case (Autodesk Fusion 360 design; units mm, degrees)
Autodesk Fusion 360 part; units mm, degrees
sketch "Sketch1" plane through (0, 0, 0) normal (0, 1, 0) x (1, 0, 0)
  line L0 (-83.15, 7.15) -> (83.15, 7.15)
  line L1 (83.15, 7.15) -> (83.15, -7.15)
  line L2 (83.15, -7.15) -> (-83.15, -7.15)
  line L3 (-83.15, -7.15) -> (-83.15, 7.15)
  line L4 (-83.15, 7.15) -> (83.15, -7.15) construction
  line L5 (83.15, 7.15) -> (-83.15, -7.15) construction
  dimension "d1" = 166.3
  dimension "d2" = 14.3
  constraint perpendicular L0 L1
  constraint parallel L0 L2
  constraint parallel L1 L3
  constraint horizontal L0
  constraint coincident L4 origin
  constraint coincident L5 origin
  measures "d1" distance of L1.end L2.end
  measures "d2" distance of L0.end L1.end
sketch "Sketch2" plane through (0, 0, 0) normal (1, 0, 0) x (0, 0, -1)
  circle A0 centre (0, 0) radius 7.15
  line L0 (7.15, 0) -> (10.65, 0)
  line L1 (-7.15, 0) -> (-10.65, 0)
  circle A1 centre (0, 0) radius 10.65
  point P0 (7.15, 0)
  point P1 (-7.15, 0)
  dimension "d4" = 3.5
  dimension "d34" = 21.3
  constraint coincident A0.centre A1.centre
  constraint coincident A0 P0
  constraint coincident P0 L0.start
  constraint coincident P1 L1.start
  constraint coincident L0.end A1
  measures "d4" distance of P1 L1.end
  measures "d34" diameter of A1
extrude "Extrude1" add sketch "Sketch2" along normal blind 140 contours A0 L0 L1 A1 | A0 L0 L1 A1
sketch "Sketch3" plane through (140, 0, 0) normal (1, 0, 0) x (0, 0, -1)
  circle A0 centre (0, 0) radius 7.15
  circle A1 centre (0, 0) radius 10.65
  line L0 (0, 0) -> (0, -10.65)
  line L1 (0, -7.15) -> (-3, -7.15)
  line L2 (0, -7.15) -> (3, -7.15)
  line L3 (-3, -7.15) -> (-3, -8.75)
  line L4 (3, -7.15) -> (3, -8.75)
  line L5 (-3, -8.75) -> (3, -8.75)
  line L6 (-3, -7.15) -> (-3, -6)
  line L7 (3, -7.15) -> (3, -5.7361)
  dimension "d7" = 3
  dimension "d8" = 3
  dimension "d9" = 1.6
  dimension "d10" = 1.6
  constraint coincident A0.centre A1.centre
  constraint coincident A1 L0.end
  constraint vertical L0
  constraint coincident L0 L1.start
  constraint coincident A0 L1.start
  constraint perpendicular L4 L5
  constraint perpendicular L5 L6
  constraint perpendicular L2 L7
  measures "d7" distance of L1.start L1.end
  measures "d8" distance of L1.start L2.end
  measures "d9" distance of L1.end L3.end
  measures "d10" distance of L2.end L4.end
extrude "Extrude2" cut sketch "Sketch3" against normal blind 42 contours A0 L1 L6 | A0 L2 L7 | L0 L2 L4 L5 | L0 L1 L3 L5
fillet "Fillet1" radius 4 2 edges at (119, -6.4902, 3) (119, -6.4902, -3)
fillet "Fillet2" radius 2 1 edges at (98, -7.15, 0)
sketch "Sketch4" plane through (0, 0, 0) normal (-1, 0, 0) x (0, 0, 1)
  circle A0 centre (0, 0) radius 7.15
  circle A1 centre (0, 0) radius 10.65
extrude "Extrude3" add sketch "Sketch4" along normal blind 2.5 contours A0 | A1
sketch "Sketch5" plane through (140, 0, 0) normal (1, 0, 0) x (0, 0, -1)
  arc A0 (4.4888, -5.5654) -> (3, -8.6789) centre (7, -8.6789) ccw
  line L0 (3, -8.6789) -> (3, -8.75)
  line L1 (3, -8.75) -> (-3, -8.75)
  line L2 (-3, -8.75) -> (-3, -8.6789)
  arc A1 (-3, -8.6789) -> (-4.4888, -5.5654) centre (-7, -8.6789) ccw
  arc A2 (4.4888, -5.5654) -> (-4.4888, -5.5654) centre (0, 0) ccw
  circle A3 centre (0, 0) radius 10.65
  line L3 (0, 0) -> (-0.0172, 16)
  line L4 (-10.65, 0) -> (-10.65, 13.2572)
  line L5 (10.65, 0) -> (10.65, 13.2572)
  line L6 (0, 13.2572) -> (-5.0089, 13.2518)
  line L7 (0, 13.2572) -> (4.9811, 13.2626)
  line L8 (0, 9.65) -> (-6, 9.6435)
  line L9 (0, 9.65) -> (8, 9.6586)
  line L10 (-5.0089, 13.2518) -> (-5.0024, 7.1882)
  line L11 (4.9811, 13.2626) -> (4.9874, 7.3746)
  line L12 (-5.0047, 9.4008) -> (-4.9656, 11.9005)
  line L13 (4.9852, 9.4112) -> (4.9825, 11.9112)
  line L14 (-4.9656, 11.9005) -> (4.9825, 11.9112)
  line L15 (-4.9656, 11.9005) -> (-2.4667, 11.8256)
  line L16 (4.9825, 11.9112) -> (2.4836, 11.8367)
  line L17 (-2.4667, 11.8256) -> (-2.4638, 9.0524)
  line L18 (2.4836, 11.8367) -> (2.4869, 8.7914)
  line L19 (-2.4644, 9.6473) -> (-5.2621, 9.6443)
  line L20 (-5.0009, 9.6446) -> (-5.0063, 14.6446)
  line L21 (2.486, 9.6526) -> (5.4045, 9.6558)
  line L22 (4.9849, 9.6553) -> (4.9796, 14.6553)
  line L23 (-5.0063, 14.6446) -> (4.9796, 14.6553)
  line L24 (-2.4667, 11.8256) -> (-2.4706, 15.4609)
  line L25 (2.4836, 11.8367) -> (2.4796, 15.6307)
  point P0 (-10.65, 0)
  point P1 (10.65, 0)
  dimension "d17" = 2.5
  dimension "d18" = 2.5
  dimension "d19" = 2.5
  dimension "d20" = 2.5
  dimension "d21" = 5
  dimension "d22" = 5
  constraint coincident A2.centre A3.centre
  constraint coincident P0 L4.start
  constraint tangent A3 L4
  constraint vertical L4
  constraint coincident P1 L5.start
  constraint tangent A3 L5
  constraint vertical L5
  constraint perpendicular L3 L9
  constraint perpendicular L3 L8
  constraint perpendicular L3 L6
  constraint perpendicular L3 L7
  constraint perpendicular L8 L10
  constraint perpendicular L9 L11
  constraint coincident A3 L12.start
  constraint coincident L10 L12.start
  constraint coincident L11 L13.start
  constraint coincident A3 L13.start
  constraint perpendicular L13 L14
  constraint perpendicular L8 L17
  constraint perpendicular L9 L18
  constraint coincident L17 L19.start
  constraint coincident L8 L19.start
  constraint coincident L8 L19.end
  constraint coincident L19 L20.start
  constraint coincident L12 L20.start
  constraint coincident L18 L21.start
  constraint coincident L9 L21.start
  constraint coincident L9 L21.end
  constraint perpendicular L13 L21
  constraint coincident L9 L22.start
  constraint coincident L11 L22.start
  constraint perpendicular L22 L23
  constraint perpendicular L23 L24
  constraint parallel L17 L24
  constraint perpendicular L23 L25
  measures "d17" distance of L12.start L12.end
  measures "d18" distance of L13.start L13.end
  measures "d19" distance of L12.end L15.end
  measures "d20" distance of L13.end L16.end
  measures "d21" distance of L20.start L20.end
  measures "d22" distance of L22.start L22.end
extrude "Extrude4" add sketch "Sketch5" against normal blind 5 contours A3 L9 L11 L13 L21 | A3 L9 L11 L13 L16 L18 L21 L22 | A3 L8 L12 L19 | L7 L11 L14 L22 L25 | L14 L16 L25 | A3 L8 L12 L15 L17 L19 | A3 L8 L17 L19 | L6 L12 L14 L20 L24 | L7 L22 L23 L25 | L14 L15 L24 | L6 L20 L23 L24
sketch "Sketch6" plane through (-2.5, 0, 0) normal (-1, 0, 0) x (0, 0, 1)
  circle A0 centre (0, 0) radius 10.65
sketch "Sketch7" plane through (0, 0.0027, -2.4963) normal (0, -0.001073, 0.999999) x (1, 0, 0)
  line L0 (140, 10.3533) -> (140, 14.65)
  line L1 (140, 14.65) -> (135, 14.65)
  line L2 (135, 14.65) -> (135, 10.3533)
  line L3 (135, 10.3533) -> (140, 10.3533)
  line L4 (137.5, 14.65) -> (137.5, 11.65)
  circle A0 centre (137.5, 11.65) radius 2.5
  circle A1 centre (137.5, 11.65) radius 2
  dimension "d25" = 3
  dimension "d26" = 5
  dimension "d31" = 4
  constraint midpoint L1 L4.start
  constraint coincident L4.end A0.centre
  constraint concentric A0 A1
  measures "d25" distance of L4.start L4.end
  measures "d26" diameter of A0
  measures "d31" diameter of A1
sketch "Sketch8" plane through (140, 0, 0) normal (1, 0, 0) x (0, 0, -1)
  arc A0 (4.4888, -5.5654) -> (3, -8.6789) centre (7, -8.6789) ccw
  line L0 (3, -8.6789) -> (3, -8.75)
  line L1 (3, -8.75) -> (-3, -8.75)
  line L2 (-3, -8.75) -> (-3, -8.6789)
  arc A1 (-3, -8.6789) -> (-4.4888, -5.5654) centre (-7, -8.6789) ccw
  arc A2 (4.4888, -5.5654) -> (-4.4888, -5.5654) centre (0, 0) ccw
  arc A3 (-5.0047, 9.4008) -> (4.9852, 9.4112) centre (0, 0) ccw
  line L3 (4.9852, 9.4112) -> (4.9796, 14.6553)
  line L4 (4.9796, 14.6553) -> (2.4806, 14.6526)
  line L5 (2.4806, 14.6526) -> (2.4852, 10.356)
  arc A4 (2.4852, 10.356) -> (-2.4652, 10.3608) centre (0, 0) ccw
  line L6 (-2.4652, 10.3608) -> (-2.4698, 14.6473)
  line L7 (-5.0063, 14.6446) -> (-5.0009, 9.6446)
  line L8 (-5.0047, 9.4008) -> (4.9852, 9.4112)
  line L9 (-2.4652, 10.3608) -> (-2.4642, 9.4034)
  line L10 (2.4852, 10.356) -> (2.4862, 9.4086)
  line L11 (-2.4698, 14.6473) -> (-5.0063, 14.6446)
  line L12 (-5.0009, 9.6446) -> (-5.0047, 9.4008)
  constraint coincident A3.start L8.start
  constraint coincident A3.end L3.start
  constraint coincident A4.end L6.start
  constraint coincident L8 L9.end
  constraint perpendicular L8 L9
  constraint coincident L5.end A4.start
  constraint coincident L8 L10.end
  constraint perpendicular L8 L10
extrude "Extrude5" cut sketch "Sketch8" against normal blind 5 contours A4 L8 L9 L10
sketch "Sketch9" plane through (0, -0.0025, 2.4544) normal (0, 0.001038, -0.999999) x (-1, 0, 0)
  line L0 (-140, 10.3633) -> (-140, 9.406)
  line L1 (-140, 9.406) -> (-135, 9.406)
  line L2 (-135, 9.406) -> (-135, 10.3633)
  circle A0 centre (-137.5, 11.6501) radius 2.5
  circle A1 centre (-137.5, 11.6501) radius 2
  line L3 (-135, 10.3633) -> (-140, 10.3633)
  line L4 (-135, 10.3633) -> (-135, 14.6499)
  line L5 (-135, 14.6499) -> (-140, 14.6499)
  line L6 (-140, 14.6499) -> (-140, 10.3633)
  line L7 (-140, 10.3633) -> (-135, 10.3633)
  point P0 (-137.5, 11.6501)
  dimension "d29" = 5
  dimension "d30" = 4
  constraint coincident P0 A0.centre
  measures "d29" diameter of A0
  measures "d30" diameter of A1
sphere "SpherePrimitive3" cut diameter 4 placed x (-1, 0, 0) y (0, 0.999999, 0.001038) z (0, 0.001038, -0.999999) at (137.5, 11.6475, 2.4665)
fillet "Fillet4" radius 2.5 4 edges at (135, 14.654, -3.7301) (140, 14.654, -3.7301) (135, 14.646, 3.738) (140, 14.646, 3.738)
fillet "Fillet5" radius 1.5 2 edges at (135, 9.9623, -3.765) (135, 9.962, 3.7657)
sphere "SpherePrimitive4" cut diameter 4 placed x (1, 0, 0) y (0, 0.999999, 0.001073) z (0, -0.001073, 0.999999) at (137.5, 11.6526, -2.4838)
chamfer "Chamfer1" distance 2 angle 45 1 edges at (140, 9.406, -0.011) tangent chain off
fillet "Fillet6" radius 10 1 edges at (138, 9.406, -0.011)
sketch "Sketch10" plane through (0, -0.0026, 2.454) normal (0, 0.001073, -0.999999) x (-1, 0, 0)
  arc A0 (-135, 12.15) -> (-140, 12.15) centre (-137.5, 12.15) ccw
  line L0 (-140, 12.15) -> (-140, 10.3634)
  line L1 (-140, 10.3634) -> (-139.0311, 10.3634)
  arc A1 (-135.9689, 10.3634) -> (-139.0311, 10.3634) centre (-137.5, 11.6501) ccw
  line L2 (-135.9689, 10.3634) -> (-135, 10.3634)
  line L3 (-135, 10.3634) -> (-133.5, 10.3634)
  spline S0 degree 3 poles (-135, 11.8996) (-135, 11.7091) (-134.956, 11.4847) (-134.8125, 11.1335) (-134.6882, 10.9439) (-134.4251, 10.6766) (-134.2404, 10.5507) (-133.8996, 10.4073) (-133.6836, 10.3634) (-133.5, 10.3634) knots 0.224259 0.224259 0.224259 0.224259 0.281416 0.281416 0.338085 0.338085 0.393945 0.393945 0.449035 0.449035 0.449035 0.449035
  line L4 (-135, 11.8996) -> (-135, 12.15)
  line L5 (-137.5, 12.15) -> (-132.5478, 12.15)
  line L6 (-137.5, 12.15) -> (-137.5, 11.35)
  line L7 (-137.5, 12.15) -> (-137.5, 12.95)
  line L8 (-137.5, 12.95) -> (-133.0281, 12.95)
  line L9 (-137.5, 11.35) -> (-133.2464, 11.35)
  line L10 (-133.2464, 11.35) -> (-133.0281, 12.95)
  dimension "d42" = 0.8
  dimension "d43" = 0.8
  constraint coincident A0.centre L5.start
  constraint perpendicular L4 L5
  constraint perpendicular L7 L8
  constraint perpendicular L6 L9
  measures "d42" distance of A0.centre L6.end
  measures "d43" distance of A0.centre L7.end
extrude "Extrude6" cut sketch "Sketch10" against normal blind 1.5 contours A0 A1 L5 L8 | S0 L4 L5 L9 L10 | A1 S0 L4 L5 L9 | A0 L5 L8 L10 | A1 L5 L7 L8 | A1 L5 L6 L9
fillet "Fillet7" radius 0.7 4 edges at (136.1929, 12.9457, 3.9679) (135.5557, 12.9473, 2.4679) (135.603, 11.3457, 3.9662) (135.2115, 11.3473, 2.4662)
sketch "Sketch11" plane through (0, 0.0027, -2.4963) normal (0, -0.001073, 0.999999) x (1, 0, 0)
  arc A0 (139.0227, 10.3533) -> (135.9773, 10.3533) centre (137.5, 11.65) ccw
  line L0 (139.0227, 10.3533) -> (140, 10.3533)
  line L1 (140, 10.3533) -> (140, 12.15)
  arc A1 (140, 12.15) -> (135, 12.15) centre (137.5, 12.15) ccw
  line L2 (135, 12.15) -> (135, 11.8908)
  spline S0 degree 3 poles (133.5, 10.3533) (133.6836, 10.3533) (133.8995, 10.3972) (134.2403, 10.5407) (134.4249, 10.6667) (134.6881, 10.9342) (134.8125, 11.1239) (134.956, 11.4755) (135, 11.7001) (135, 11.8908) knots 0.449206 0.449206 0.449206 0.449206 0.50428 0.50428 0.560152 0.560152 0.616862 0.616862 0.674077 0.674077 0.674077 0.674077
  line L3 (133.5, 10.3533) -> (135, 10.3533)
  line L4 (135, 10.3533) -> (135.9773, 10.3533)
  line L5 (137.5, 12.95) -> (133.0281, 12.95)
  line L6 (137.5, 12.95) -> (133.0281, 12.95)
  line L7 (137.5, 11.35) -> (133.2464, 11.35)
  line L8 (133.2464, 11.35) -> (133.0281, 12.95)
  line L9 (137.5, 12.95) -> (137.5, 11.35)
  point P0 (137.5, 12.95)
  point P1 (133.0281, 12.95)
  point P2 (137.5, 11.35)
  point P3 (133.2464, 11.35)
  constraint coincident P0 L5.start
  constraint coincident P1 L5.end
  constraint coincident P2 L7.start
  constraint coincident P3 L7.end
extrude "Extrude7" cut sketch "Sketch11" against normal blind 1.5 contours A0 L5 L6 L7 L9 | A0 A1 L2 S0 L5 L6 L7 | A1 L2 S0 L5 L6 L7 L8
fillet "Fillet8" radius 0.7 4 edges at (136.1933, 12.9542, -3.9824) (135.5558, 12.9526, -2.4824) (135.6035, 11.3542, -3.9842) (135.2132, 11.3526, -2.4842)
sketch "Sketch12" plane through (140, 0, 0) normal (1, 0, 0) x (0, 0, -1)
  line L0 (-2.4621, 7.4034) -> (-2.4652, 10.3608)
  line L1 (-2.4652, 10.3608) -> (-2.4671, 12.1473)
  line L2 (-2.4671, 12.1473) -> (-5.0036, 12.1446)
  line L3 (-5.0036, 12.1446) -> (-5.0009, 9.6446)
  line L4 (-5.0009, 9.6446) -> (-5.0047, 9.4008)
  arc A0 (-5.0047, 9.4008) -> (4.9852, 9.4112) centre (0, 0) ccw
  line L5 (4.9852, 9.4112) -> (4.9823, 12.1553)
  line L6 (4.9823, 12.1553) -> (2.4833, 12.1526)
  line L7 (2.4833, 12.1526) -> (2.4852, 10.356)
  line L8 (2.4852, 10.356) -> (2.4883, 7.4086)
  line L9 (2.4883, 7.4086) -> (-2.4621, 7.4034)
  arc A1 (4.4888, -5.5654) -> (3, -8.6789) centre (7, -8.6789) ccw
  line L10 (3, -8.6789) -> (3, -8.75)
  line L11 (3, -8.75) -> (-3, -8.75)
  line L12 (-3, -8.75) -> (-3, -8.6789)
  arc A2 (-3, -8.6789) -> (-4.4888, -5.5654) centre (-7, -8.6789) ccw
  arc A3 (4.4888, -5.5654) -> (-4.4888, -5.5654) centre (0, 0) ccw
  circle A4 centre (0, 0) radius 8.65
  line L13 (-8.65, 0) -> (-10.65, 0.0156)
  line L14 (8.65, 0) -> (10.65, 0)
  point P0 (10.65, 0)
  dimension "d50" = 17.3
  constraint concentric A0 A4
  constraint coincident A4 L13.start
  constraint coincident A0 L13.end
  constraint coincident A4 L14.start
  constraint coincident P0 L14.end
  constraint horizontal L14
  measures "d50" diameter of A4
extrude "Extrude8" cut sketch "Sketch12" against normal blind 44 contours A0 A1 L10 L11 L12 A2 A4 L13 L14
sketch "Sketch13" plane through (96, 0, 0) normal (1, 0, 0) x (0, 0, -1)
  arc A0 (3.0425, -8.0973) -> (3, -8.6789) centre (7, -8.6789) ccw
  line L0 (3, -8.6789) -> (3, -8.75)
  line L1 (3, -8.75) -> (-3, -8.75)
  line L2 (-3, -8.75) -> (-3, -8.6789)
  arc A1 (-3, -8.6789) -> (-3.0425, -8.0973) centre (-7, -8.6789) ccw
  arc A2 (-8.65, 0) -> (-3.0425, -8.0973) centre (0, 0) ccw
  line L3 (-8.65, 0) -> (-10.65, 0.0156)
  arc A3 (-10.65, 0.0156) -> (10.65, 0) centre (0, 0) ccw
  line L4 (10.65, 0) -> (8.65, 0)
  arc A4 (3.0425, -8.0973) -> (8.65, 0) centre (0, 0) ccw
  line L5 (-0.0078, -10.65) -> (-0.0078, -9.65)
  circle A5 centre (-0.0078, -9.65) radius 0.625
  line L6 (-9.65, 0.0078) -> (-9.5319, -1.4926)
  line L7 (-9.65, 0.0078) -> (-8.145, 0.0078) construction
  circle A6 centre (-9.5319, -1.4926) radius 0.625
  line L8 (9.65, 0) -> (9.5319, -1.5004)
  line L9 (9.65, 0) -> (11.155, 0) construction
  circle A7 centre (9.5319, -1.5004) radius 0.625
  dimension "d53" = 1
  dimension "d54" = 1.25
  dimension "d55" = 85.5
  dimension "d56" = 1.505
  dimension "d57" = 1.25
  dimension "d58" = 94.5
  dimension "d59" = 1.505
  dimension "d60" = 1.25
  constraint midpoint A3 L5.start
  constraint coincident L5.end A5.centre
  constraint midpoint L3 L6.start
  constraint horizontal L7
  constraint coincident L6.end A6.centre
  constraint midpoint L4 L8.start
  constraint horizontal L9
  constraint coincident L8.end A7.centre
  measures "d53" distance of L5.start L5.end
  measures "d54" diameter of A5
  measures "d55" angle of L6 L7
  measures "d56" distance of L6.start L6.end
  measures "d57" diameter of A6
  measures "d58" angle of L8 L9
  measures "d59" distance of L8.start L8.end
  measures "d60" diameter of A7
sphere "SpherePrimitive5" cut diameter 1.25 placed x (0, 0, -1) y (0, 1, 0) z (1, 0, 0) at (96, -1.4926, 9.5319)
sphere "SpherePrimitive6" cut diameter 1.25 placed x (0, 0, -1) y (0, 1, 0) z (1, 0, 0) at (96, -9.65, 0.0078)
sphere "SpherePrimitive7" cut diameter 1.25 placed x (0, 0, -1) y (0, 1, 0) z (1, 0, 0) at (96, -1.5004, -9.5319)
sketch "Sketch14" plane through (0, 0, 0) normal (0, -1, 0) x (1, 0, 0)
  line L0 (140, -10.65) -> (140, -8.65)
  line L1 (140, -8.65) -> (96, -8.65)
  line L2 (96, -8.65) -> (96, -10.65)
  line L3 (96, -10.65) -> (140, -10.65)
  line L4 (96, -9.65) -> (118, -9.65)
  circle A0 centre (118, -9.65) radius 0.5625
  dimension "d64" = 22
  dimension "d65" = 1.125
  constraint coincident L4.end A0.centre
  measures "d64" distance of L4.start L4.end
  measures "d65" diameter of A0
extrude "Extrude9" cut sketch "Sketch14" against normal blind 2 contours A0
fillet "Fillet9" radius 0.25 1 edges at (117.4756, 0, -9.4466)
sketch "Sketch15" plane through (96, 0, 0) normal (1, 0, 0) x (0, 0, -1)
  circle A0 centre (9.5319, -1.5004) radius 0.625
  circle A1 centre (-0.0078, -9.65) radius 0.625
  circle A2 centre (-9.5319, -1.4926) radius 0.625
  arc A3 (3.0425, -8.0973) -> (3, -8.6789) centre (7, -8.6789) ccw
  line L0 (3, -8.6789) -> (3, -8.75)
  line L1 (3, -8.75) -> (-3, -8.75)
  line L2 (-3, -8.75) -> (-3, -8.6789)
  arc A4 (-3, -8.6789) -> (-3.0425, -8.0973) centre (-7, -8.6789) ccw
  arc A5 (-8.65, 0) -> (-3.0425, -8.0973) centre (0, 0) ccw
  line L3 (-8.65, 0) -> (-10.65, 0.0156)
  arc A6 (-10.65, 0.0156) -> (10.65, 0) centre (0, 0) ccw
  line L4 (10.65, 0) -> (8.65, 0)
  arc A7 (3.0425, -8.0973) -> (8.65, 0) centre (0, 0) ccw
  arc A8 (-3.0425, -8.0973) -> (3.0425, -8.0973) centre (0, 7.7166) ccw
  constraint coincident A3.start A7.start
  constraint coincident A4.end A5.end
extrude "Extrude10" cut sketch "Sketch15" along normal blind 4.5 contours A3 L0 L1 L2 A4 A8
